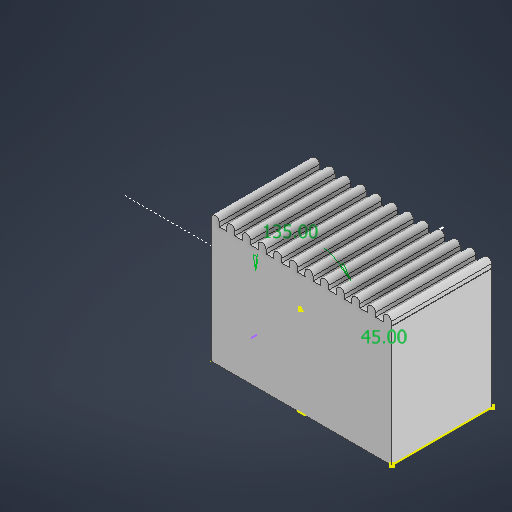
# Autodesk Inventor part: Feet
Saved by Autodesk Inventor 2026.3 (Build 303398000, 398)
## iProperties
Created: 2026-10-03
Part Number: Feet
Material: Generic
Document SubType Name: Modeling
Designer: joaqu
Density: 1 g/cm^3
Appearance: Default
Author: joaqu
Autodesk Inventor part; units mm, degrees
ref_plane "YZ Plane" through (0, 0, 0) normal (1, 0, 0) x (0, 1, 0)
ref_plane "XZ Plane" through (0, 0, 0) normal (0, 1, 0) x (-1, 0, 0)
sketch "Sketch1" plane through (0, 0, 0) normal (0, 1, 0) x (-1, 0, 0)
  line L0 (0, 0) -> (45, 0)
  line L1 (45, 0) -> (45, -25)
  line L2 (45, -25) -> (0, -25)
  line L3 (0, -25) -> (0, 0)
  dimension "d0" = 45
  dimension "d1" = 25
  constraints: 8 end point, 2 parallel, 1 horizontal, 1 perpendicular
  measures "d0" distance of L1.end L2.end
  measures "d1" distance of L0.end L1.end
extrude "Extrusion1" add sketch "Sketch1" along normal blind 30
sketch "Sketch2" plane through (-45, 0, 0) normal (0, 0, 1) x (1, 0, 0)
  point P0 (45, 0)
sketch "Sketch3" plane through (0, 30, 0) normal (0, 1, 0) x (1, 0, 0)
  line L0 (0, 25) -> (-45, 25) projected
  line L1 (-45, 0) -> (0, 0) projected
  line L2 (-45, 25) -> (-43, 25)
  line L3 (-43, 25) -> (-43, 0)
  line L4 (-43, 0) -> (-45, 0)
  line L5 (-45, 0) -> (-45, 25)
  dimension "d4" = 2
  constraints: 8 end point, 2 parallel, 1 horizontal, 1 perpendicular, 1 point on line
  measures "d4" distance of L3.end L4.end
extrude "Extrusion2" add sketch "Sketch3" along normal blind 2
fillet "Fillet1" radius 1 1 edges at (-43, 32, -12.5)
fillet "Fillet2" radius 1 1 edges at (-45, 32, -12.5)
pattern_linear "Rectangular Pattern1" count 12 spacing 3.9 along (1, 0, 0) of "Extrusion2", "Fillet1", "Fillet2"
sketch "Sketch8" plane through (0, 0, -25) normal (0, 0, -1) x (-1, 0, 0)
  point P0 (0, 0)
sketch "Sketch9" plane through (0, 0, 0) normal (0, -1, 0) x (1, 0, 0)
  line L0 (-45, -25) -> (-45, 0) projected
  line L1 (-45, -12.5) -> (0, -12.5)
  line L2 (0, 0) -> (0, -25) projected
  line L3 (-22.5, -12.5) -> (-22.55, 0)
  line L4 (-23.5, 0) -> (-21.6, 0) projected
  line L5 (-22.5, -12.5) -> (-22.4512, -24.6959)
  circle A0 centre (-22.5, -12.5) radius 4.2662
  constraints: 6 end point, 4 midpoint, 1 centre point, 1 coincident, 1 point on line
sketch "Sketch10" plane through (0, 0, -25) normal (0, 0, -1) x (-1, 0, 0)
  line L0 (45, 0) -> (0, 0) projected
  line L1 (45, 0) -> (12.1705, 32.8295)
  line L2 (45, 0) -> (91.428, 0) construction
  dimension "d21" = 135
  constraints: 4 end point, 1 equal length, 1 horizontal
  measures "d21" angle of L2 L1
ref_plane "Work Plane2" through (-45, 0, -25) normal (-0.7071068, 0.7071068, 0) x (0.7071068, 0.7071068, 0)
sketch "Sketch11" plane through (-45, 0, -25) normal (-0.7071068, 0.7071068, 0) x (0.7071068, 0.7071068, 0)
  circle A0 centre (15.8891, -12.4958) radius 6.225
  point P0 (31.8198, -25)
  dimension "d23" = 12.45
  constraints: 1 centre point
  measures "d23" diameter of A0
sketch "Sketch12" plane through (-45, 0, 0) normal (0, 0, 1) x (1, 0, 0)
  point P0 (45, 0)
sketch "Sketch13" plane through (0, 0, -25) normal (0, 0, -1) x (-1, 0, 0)
  line L0 (45, 0) -> (0, 0) projected
  line L1 (22.5, 0) -> (33.7518, 11.2518)
  line L2 (22.5, 0) -> (38.4125, 0) construction
  dimension "d24" = 45
  constraints: 4 end point, 1 equal length, 1 horizontal, 1 midpoint
  measures "d24" angle of L2 L1
sketch "Sketch14" plane through (-45, 0, -25) normal (-0.7071068, 0.7071068, 0) x (0.7071068, 0.7071068, 0)
  line L0 (15.9097, 0.0002) -> (15.9097, -26.2133)
  point P0 (31.8198, -25)
  constraints: 2 end point, 1 vertical
extrude "Extrusion4" cut sketch "Sketch11" against normal blind 30
body "Solid1"
